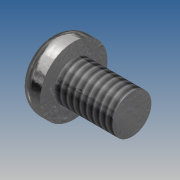
# Autodesk Inventor part: S45 ONYX STANDARD METAL GEAR SERVO (M3 SCREW)
Saved by Autodesk Inventor 2022.1 (Build 261234000, 234)
## iProperties
Created: 2021-08-02
Part Number: S45 ONYX STANDARD METAL GEAR SERVO (M3 SCREW)
Material: Steel, Galvanized
Document SubType Name: Modeling
Designer: dotwibo2
Mass: 0.422474 g
Surface Area: 1.11689 cm^2
Volume: 0.0538184 cm^3
Density: 7.85 g/cm^3
Appearance: Galvanized
Description: DU-BRO SHEET METAL SCREW
Size: #2 X 0.500
UOFM: EACH
MAKE_OR_BUY: M
PURCH_SIZE: #2 X 0.500
PURCH_QTY: 1
PURCH_UOFM: EACH
Author: dotwibo2
Title: DU-BRO SHEET METAL SCREW
Autodesk Inventor part; units mm, degrees
ref_plane "YZ Plane" through (0, 0, 0) normal (1, 0, 0) x (0, 1, 0)
ref_plane "XZ Plane" through (0, 0, 0) normal (0, 1, 0) x (-1, 0, 0)
ref_plane "XY Plane" through (0, 0, 0) normal (0, 0, 1) x (1, 0, 0)
sketch "Sketch1" plane through (0, 0, 0) normal (0, 0, 1) x (1, 0, 0)
  line L0 (-4.0865, 0) -> (10.1056, 0) projected
  line L1 (0, -0.5647) -> (0, 3.3879) construction
  arc A0 (-0.6881, 2.605) -> (-1.873, 1.5949) centre (-0.6881, 1.405) ccw
  line L2 (-0.6881, 2.605) -> (0, 2.605)
  line L3 (0, 2.605) -> (0, 1.5)
  line L4 (0, 1.5) -> (4.5, 1.5)
  arc A1 (-1.873, 1.5949) -> (-2, 0) centre (8.0781, 0) ccw
  line L5 (4.5, 1.5) -> (4.5, 0)
  point P0 (0, 0)
  dimension "d0" = 3
  dimension "d1" = 1.2
  dimension "d4" = 4.5
  dimension "d5" = 2
  dimension "d6" = 0.127
  dimension "d7" = 5.21
  dimension "d21" = 6.5
  constraints: 8 end point, 4 point on circle, 3 point on line, 2 centre point, 2 horizontal, 2 tangent, 2 vertical, 1 collinear
  measures "d0" diameter of L4 L0
  measures "d1" radius of A0
  measures "d4" distance from line of L5.end L3
  measures "d5" distance from line of L3 A1.end
  measures "d6" horizontal distance of A1.end A0.end
  measures "d7" diameter of L2.end L0
  measures "d21" distance of L5.end A1.end
revolve "Revolution1" add sketch "Sketch1" angle 360 about axis through (-10, 0, 0) along (1, 0, 0)
thread "Thread1" size "M3x0.5" class "6g" standard "ANSI Metric M Profile" length 12.7
sketch "Sketch3" plane through (0, 0, 0) normal (0, 1, 0) x (-1, 0, 0)
  line L0 (2.35, 2.325) -> (2.35, -2.325)
  line L1 (2.35, -2.325) -> (0.35, -0.325)
  line L2 (0.35, -0.325) -> (0.35, 0.325)
  line L3 (0.35, 0.325) -> (2.35, 2.325)
  line L4 (2.1, 0) -> (-0.35, 0) construction
  line L5 (0, -2.555) -> (0, 2.555) construction
  point P0 (0, 0)
  dimension "d26" = 0.35
  dimension "d27" = 0.65
  dimension "d28" = 90
  dimension "d29" = 2
  constraints: 8 end point, 2 vertical, 1 other
  measures "d26" distance between parallel lines of L5 L2
  measures "d27" distance of L1.end L2.end
  measures "d28" angle of L1 L3
  measures "d29" distance between parallel lines of L2 L0
extrude "Extrusion2" cut sketch "Sketch3" along normal mid plane 0.65
pattern_circular "Circular Pattern1" count 2 over 90 about axis through (-10, 0, 0) along (1, 0, 0) of "Extrusion2"
body "Solid1"
